Autodesk Fusion 360 part; units mm, degrees
(part 3 of 3)
component "Reference_ScrewCell_0_1" placed x (1, 0, 0) y (0, 1, 0) z (0, 0, 1) at (0, 0, 0) in component "Reference_CellJointScrews"
component "Reference_ScrewCell_0_2" placed x (1, 0, 0) y (0, 1, 0) z (0, 0, 1) at (0, 0, 0) in component "Reference_CellJointScrews"
component "Reference_ScrewCell_0_3" placed x (1, 0, 0) y (0, 1, 0) z (0, 0, 1) at (0, 0, 0) in component "Reference_CellJointScrews"
component "Reference_ScrewRim_0" placed x (1, 0, 0) y (0, 1, 0) z (0, 0, 1) at (0, 0, 0) in component "Reference_RimScrews"
component "Reference_ScrewRim_1" placed x (1, 0, 0) y (0, 1, 0) z (0, 0, 1) at (0, 0, 0) in component "Reference_RimScrews"
component "Reference_ScrewRim_2" placed x (1, 0, 0) y (0, 1, 0) z (0, 0, 1) at (0, 0, 0) in component "Reference_RimScrews"
component "Reference_ScrewRim_3" placed x (1, 0, 0) y (0, 1, 0) z (0, 0, 1) at (0, 0, 0) in component "Reference_RimScrews"
component "Reference_ScrewRim_4" placed x (1, 0, 0) y (0, 1, 0) z (0, 0, 1) at (0, 0, 0) in component "Reference_RimScrews"
component "Reference_ScrewRim_5" placed x (1, 0, 0) y (0, 1, 0) z (0, 0, 1) at (0, 0, 0) in component "Reference_RimScrews"
component "Reference_ScrewRim_6" placed x (1, 0, 0) y (0, 1, 0) z (0, 0, 1) at (0, 0, 0) in component "Reference_RimScrews"
component "Reference_ScrewRim_7" placed x (1, 0, 0) y (0, 1, 0) z (0, 0, 1) at (0, 0, 0) in component "Reference_RimScrews"
component "Reference_ScrewPanel_0" placed x (1, 0, 0) y (0, 1, 0) z (0, 0, 1) at (0, 0, 0) in component "Reference_PanelScrews"
component "Reference_ScrewPanel_1" placed x (1, 0, 0) y (0, 1, 0) z (0, 0, 1) at (0, 0, 0) in component "Reference_PanelScrews"
component "Reference_ScrewPanel_2" placed x (1, 0, 0) y (0, 1, 0) z (0, 0, 1) at (0, 0, 0) in component "Reference_PanelScrews"
component "Reference_ScrewPanel_3" placed x (1, 0, 0) y (0, 1, 0) z (0, 0, 1) at (0, 0, 0) in component "Reference_PanelScrews"
component "Reference_ScrewPanel_4" placed x (1, 0, 0) y (0, 1, 0) z (0, 0, 1) at (0, 0, 0) in component "Reference_PanelScrews"
component "Reference_ScrewPanel_5" placed x (1, 0, 0) y (0, 1, 0) z (0, 0, 1) at (0, 0, 0) in component "Reference_PanelScrews"
component "Reference_ScrewPanel_6" placed x (1, 0, 0) y (0, 1, 0) z (0, 0, 1) at (0, 0, 0) in component "Reference_PanelScrews"
component "Reference_ScrewPanel_7" placed x (1, 0, 0) y (0, 1, 0) z (0, 0, 1) at (0, 0, 0) in component "Reference_PanelScrews"
equation "d33 = -( 2.00 mm )"
equation "d37 = -( 2.00 mm )"
equation "d41 = -( 2.00 mm )"
equation "d45 = -( 2.00 mm )"
equation "d49 = -( 2.00 mm )"
equation "d53 = -( 2.00 mm )"
equation "d57 = -( 2.00 mm )"
equation "d61 = -( 2.00 mm )"
equation "d65 = -( 2.00 mm )"
equation "d69 = -( 2.00 mm )"
equation "d73 = -( 2.00 mm )"
equation "d77 = -( 2.00 mm )"
equation "d81 = -( 2.00 mm )"
equation "d85 = -( 2.00 mm )"
equation "d89 = -( 2.00 mm )"
equation "d93 = -( 2.00 mm )"
equation "d97 = -( 2.00 mm )"
equation "d101 = -( 2.00 mm )"
equation "d105 = -( 2.00 mm )"
equation "d109 = -( 2.00 mm )"
equation "d113 = -( 2.00 mm )"
equation "d117 = -( 2.00 mm )"
equation "d121 = -( 2.00 mm )"
equation "d125 = -( 2.00 mm )"
equation "d183 = -( 7.10 mm )"
equation "d191 = -( 7.10 mm )"
equation "d199 = -( 7.10 mm )"
equation "d207 = -( 7.10 mm )"
equation "d669 = -( 10.00 mm )"
equation "d677 = -( 10.00 mm )"
equation "d685 = -( 10.00 mm )"
equation "d693 = -( 10.00 mm )"
equation "d705 = -( 2.00 mm )"
equation "d713 = -( 2.00 mm )"
equation "d721 = -( 2.00 mm )"
equation "d729 = -( 2.00 mm )"
equation "d737 = -( 2.00 mm )"
equation "d745 = -( 2.00 mm )"
equation "d753 = -( 2.00 mm )"
equation "d761 = -( 2.00 mm )"
equation "d769 = -( 2.00 mm )"
equation "d777 = -( 2.00 mm )"
equation "d785 = -( 2.00 mm )"
equation "d793 = -( 2.00 mm )"
equation "d801 = -( 2.00 mm )"
equation "d809 = -( 2.00 mm )"
equation "d817 = -( 2.00 mm )"
equation "d825 = -( 2.00 mm )"
